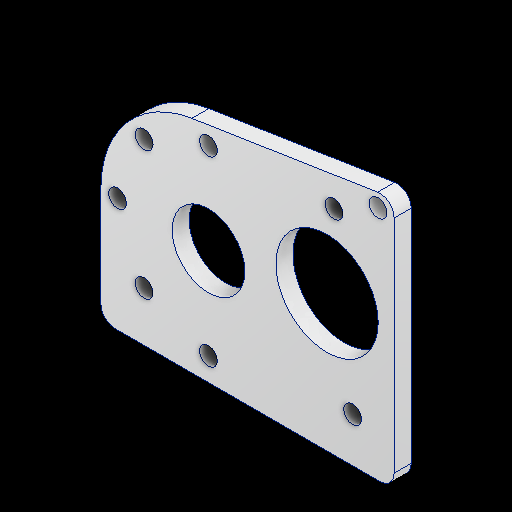
# Autodesk Inventor part: INTK_006_kraken holder
Saved by Autodesk Inventor 2027.1 (Build 311270010, 270A)
## iProperties
Created: 2026-11-21
Part Number: INTK_006_kraken holder
Material: Aluminum 6061
Document SubType Name: Modeling
Designer: Stanley Ruangsuwan
Density: 2.7 g/cm^3
Appearance: Aluminum - Flat
Author: Stanley Ruangsuwan
Autodesk Inventor part; units mm, degrees
ref_plane "YZ Plane" through (0, 0, 0) normal (1, 0, 0) x (0, 1, 0)
ref_plane "XZ Plane" through (0, 0, 0) normal (0, 1, 0) x (-1, 0, 0)
ref_plane "XY Plane" through (0, 0, 0) normal (0, 0, 1) x (1, 0, 0)
sketch "Sketch1" plane through (0, 0, 0) normal (0, 0, 1) x (1, 0, 0)
  line L0 (0, 0) -> (0, 70.3673)
  circle A0 centre (-16.7849, 59.5312) radius 6.35 construction
  circle A1 centre (-51.8403, 31.8516) radius 30.0609
  line L1 (0, 0) -> (-81.9012, 0)
  line L2 (-81.9012, 31.8516) -> (-81.9012, 0)
  line L3 (0, 70.3673) -> (-56.4759, 61.5529)
  circle A2 centre (28.3221, 40.661) radius 34.29 construction
  line L4 (-21.7686, 55.5961) -> (-28.2474, 50.4804) construction
  line L5 (-10.9268, 57.0805) -> (-3.3114, 53.8946) construction
  circle A3 centre (-11.6104, 12.4455) radius 6.35 construction
  line L6 (-17.3298, 15.2044) -> (-24.7649, 18.791) construction
  line L7 (0.3175, 20.8735) -> (-6.4244, 16.1098) construction
  circle A4 centre (-11.6104, 12.4455) radius 2.4892
  circle A5 centre (-16.7849, 59.5312) radius 2.4892
  circle A6 centre (-51.8403, 31.8516) radius 10.16
  circle A7 centre (-51.8403, 57.2516) radius 2.4892
  circle A8 centre (-69.8008, 49.8121) radius 2.4892
  circle A9 centre (-77.2403, 31.8516) radius 2.4892
  circle A10 centre (-69.8008, 13.8911) radius 2.4892
  circle A11 centre (-51.8403, 6.4516) radius 2.4892
  circle A12 centre (-18.7446, 38.1) radius 14.2875
  circle A13 centre (-4.5153, 65.9025) radius 6.35 construction
  circle A14 centre (-4.5153, 65.9025) radius 2.4892
  dimension "d28" = 12.7
  dimension "d0" = 70.3673
  dimension "d3" = 12.7
  dimension "d4" = 60.1218
  dimension "d6" = 31.8516
  dimension "d10" = 51.8403
  dimension "d11" = 68.58
  dimension "d12" = 80.1624
  dimension "d13" = 80.645
  dimension "d14" = 8.255
  dimension "d15" = 4.9784
  dimension "d16" = 20.32
  dimension "d17" = 25.4
  dimension "d20" = 180
  dimension "d25" = 28.575
  dimension "d26" = 33.6804
  dimension "d27" = 38.1
  dimension "d29" = 4.9784
  dimension "d30" = 13.8252
  constraints: 16 end point, 14 centre point, 10 point on circle, 8 point on line, 4 coincident, 3 equal length, 3 equal radius, 2 tangent, 2 vertical, 1 horizontal, 1 vertical alignment, 12 other
  measures "d0" distance of L0.start L0.end
  measures "d3" diameter of A0
  measures "d4" diameter of A1
  measures "d6" distance from line of L1 A1.centre
  measures "d10" distance from line of L0 A1.centre
  measures "d11" diameter of A2
  measures "d12" horizontal distance of A1.centre A2.centre
  measures "d13" distance of A1.centre A2.centre
  measures "d14" distance of L4.start L4.end
  measures "d15" diameter of A4
  measures "d16" diameter of A6
  measures "d17" distance of A6.centre A7.centre
  measures "d25" diameter of A12
  measures "d26" distance of A6.centre A12.centre
  measures "d27" distance from line of L1 A12.centre
  measures "d29" diameter of A14
  measures "d30" distance of A0.centre point (-4.515, 65.903)
extrude "Extrusion1" add sketch "Sketch1" along normal blind 4.7625 contours L1 L2 A1 A12 L3 L0 | A1 A12 picked at (-34.1486, 21.5717)
fillet "Fillet1" radius 4 3 edges at (0, 0, 2.3813) (0, 70.3673, 2.3813) (-81.9012, 0, 2.3813)
body "Solid1"
